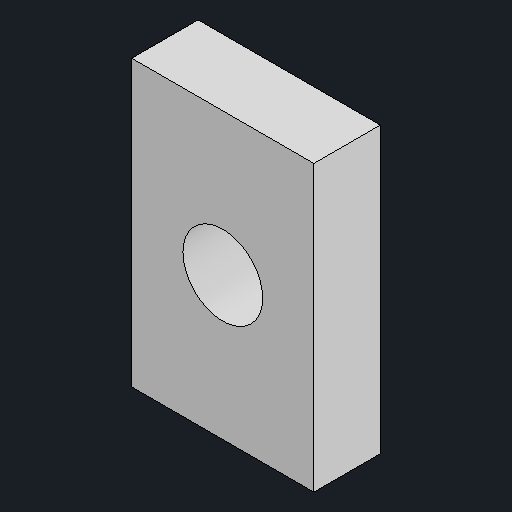
# Autodesk Inventor part: monotaro-M5-profile-T-nut-envelope
Saved by Autodesk Inventor 2027.1 (Build 311270010, 270A)
## iProperties
Created: 2026-11-14
Part Number: monotaro-M5-profile-T-nut-envelope
Material: Generic
Document SubType Name: Modeling
Designer: queezz
Density: 1 g/cm^3
Appearance: Default
Author: queezz
Autodesk Inventor part; units mm, degrees
ref_plane "YZ Plane" through (0, 0, 0) normal (1, 0, 0) x (0, 1, 0)
ref_plane "XZ Plane" through (0, 0, 0) normal (0, 1, 0) x (-1, 0, 0)
ref_plane "XY Plane" through (0, 0, 0) normal (0, 0, 1) x (1, 0, 0)
sketch "Sketch1" plane through (0, 0, 0) normal (0, 0, 1) x (1, 0, 0)
  line L0 (-4.8, -7.5) -> (4.8, -7.5)
  line L1 (4.8, -7.5) -> (4.8, 7.5)
  line L2 (4.8, 7.5) -> (-4.8, 7.5)
  line L3 (-4.8, 7.5) -> (-4.8, -7.5)
  constraints: 8 end point, 2 parallel, 1 horizontal, 1 perpendicular
extrude "Nominal 10 mm slot nut body" add sketch "Sketch1" against normal blind 3.5
sketch "Sketch2" plane through (0, 0, 0) normal (0, 0, 1) x (1, 0, 0)
  circle A0 centre (0, 0) radius 2.1
  constraints: 1 centre point
extrude "M5 minor bore" cut sketch "Sketch2" against normal blind 3.5
body "Solid1"
